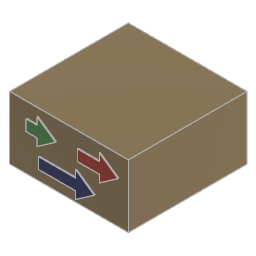
Bloque_de_pared_Con_Flechas (Autodesk Fusion 360 design; units mm, degrees)
Autodesk Fusion 360 part; units mm, degrees
box "CajaPrimitiva1" add length 320 width 320 height 170 placed x (0, 1, 0) y (-1, 0, 0) z (0, 0, 1) at (280, -40, 0) makes body 1
sketch "Boceto2" plane through (0, -40, 0) normal (0, -1, 0) x (1, 0, 0)
  line L0 (-40, 170) -> (-40, 0)
  line L1 (-40, 0) -> (280, 0)
  line L2 (280, 0) -> (280, 170)
  line L3 (280, 170) -> (-40, 170)
  line L4 (5.6013, 130) -> (5.6013, 100)
  line L5 (5.6013, 130) -> (35.6013, 130)
  line L6 (5.6013, 100) -> (35.6013, 100)
  line L7 (35.6013, 100) -> (35.6013, 80)
  line L8 (35.6013, 150) -> (85.6013, 115)
  line L9 (35.6013, 80) -> (85.6013, 115)
  line L10 (35.6013, 80) -> (35.6013, 100)
  line L11 (35.6013, 130) -> (35.6013, 150)
  line L12 (203.9569, 79.2301) -> (253.9569, 114.2301)
  line L13 (203.9569, 129.2301) -> (203.9569, 149.2301)
  line L14 (203.9569, 79.2301) -> (203.9569, 99.2301)
  line L15 (203.9569, 149.2301) -> (253.9569, 114.2301)
  line L16 (143.9569, 129.2301) -> (143.9569, 99.2301)
  line L17 (203.9569, 99.2301) -> (203.9569, 79.2301)
  line L18 (143.9569, 129.2301) -> (203.9569, 129.2301)
  line L19 (143.9569, 99.2301) -> (203.9569, 99.2301)
  line L20 (139.797, 78.3976) -> (189.797, 43.3976)
  line L21 (139.797, 28.3976) -> (139.797, 8.3976)
  line L22 (139.797, 58.3976) -> (139.797, 78.3976)
  line L23 (139.797, 8.3976) -> (189.797, 43.3976)
  line L24 (139.797, 8.3976) -> (139.797, 28.3976)
  line L25 (39.797, 28.3976) -> (139.797, 28.3976)
  line L26 (39.797, 58.3976) -> (139.797, 58.3976)
  line L27 (39.797, 58.3976) -> (39.797, 28.3976)
  dimension "d8" = 30
  dimension "d12" = 30
  dimension "d13" = 30
  dimension "d16" = 70
  dimension "d18" = 30
  dimension "d21" = 70
  dimension "d22" = 60
  dimension "d23" = 60
  dimension "d24" = 30
  dimension "d25" = 70
  dimension "d26" = 100
  dimension "d27" = 100
  constraint vertical L4
  constraint perpendicular L4 L5
  constraint perpendicular L4 L6
  constraint perpendicular L5 L11
  constraint collinear L10 L11
  constraint vertical L16
  constraint collinear L13 L14
  constraint perpendicular L16 L18
  constraint collinear L22 L24
  constraint perpendicular L26 L27
  measures "d8" distance of L4.start L4.end
  measures "d12" distance of L4.start L5.end
  measures "d13" distance of L4.end L6.end
  measures "d16" distance of L7.end L8.start
  measures "d18" distance of L16.start L16.end
  measures "d21" distance of L13.end L12.start
  measures "d22" distance of L16.start L13.start
  measures "d23" distance of L14.end L16.end
  measures "d24" distance of L26.start L25.start
  measures "d25" distance of L21.end L20.start
  measures "d26" distance of L22.start L26.start
  measures "d27" distance of L21.start L25.start
extrude "Extruir1" add sketch "Boceto2" along normal blind 2 separate body contours L4 L5 L6 L7 L8 L9 L10 L11 | L12 L13 L14 L15 L16 L17 L18 L19 | L20 L21 L22 L23 L24 L25 L26 L27 makes body 2 at (52.268, -40, 115) makes body 3 at (163.9569, -40, 119.2301) makes body 4 at (73.1304, -40, 48.3976)
equation "L_corta = 30 mm"
equation "L_media = 60 mm"
equation "L_larga = 100 mm"
equation "d12 = L_corta"
equation "d13 = L_corta"
equation "d22 = L_media"
equation "d23 = L_media"
equation "d26 = L_larga"
equation "d27 = L_larga"
